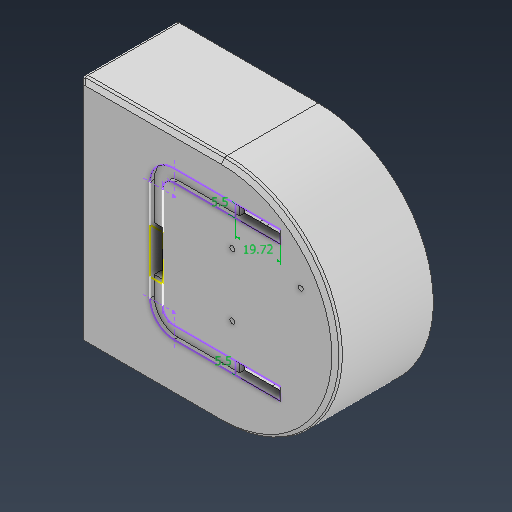
# Autodesk Inventor part: motor_housing
Saved by Autodesk Inventor 2026 (Build 300175050, 175E)
## iProperties
Created: 2025-09-28
Part Number: motor_housing
Material: Generic
Document SubType Name: Modeling
Designer: PK
Density: 1 g/cm^3
Appearance: Default
Author: PK
Autodesk Inventor part; units mm, degrees
ref_plane "YZ Plane" through (0, 0, 0) normal (1, 0, 0) x (0, 1, 0)
ref_plane "XZ Plane" through (0, 0, 0) normal (0, 1, 0) x (-1, 0, 0)
ref_plane "XY Plane" through (0, 0, 0) normal (0, 0, 1) x (1, 0, 0)
sketch "Sketch2" plane through (0, 0, 0) normal (0, 0, 1) x (1, 0, 0)
  line L0 (10.41, 16.56) -> (-35.41, 16.56)
  line L1 (-35.41, 16.56) -> (-35.41, -16.56)
  line L2 (-35.41, -12.56) -> (-25.61, -12.56)
  line L3 (-35.41, 12.56) -> (10.41, 12.56)
  line L4 (10.41, 16.56) -> (14.41, 16.56)
  line L5 (14.41, 16.56) -> (14.41, -16.56)
  line L6 (-35.41, 16.56) -> (-39.41, 16.56)
  line L7 (-39.41, 16.56) -> (-39.41, -16.56)
  circle A0 centre (0, 0) radius 3.15
  circle A1 centre (0, 0) radius 1.1
  line L8 (0.39, -12.56) -> (10.41, -12.56)
  line L9 (-5.61, -12.56) -> (0.39, -12.56)
  line L10 (-14.11, -12.56) -> (-5.61, -12.56)
  line L11 (-25.61, -12.56) -> (-14.11, -12.56)
  line L12 (-29.819493, 9.86) -> (-18.419493, 9.86)
  line L13 (-18.419493, 9.86) -> (-18.419493, -9.86)
  line L14 (-18.419493, -9.86) -> (-29.819493, -9.86)
  line L15 (-29.819493, -9.86) -> (-29.819493, 9.86)
  line L16 (-35.41, 12.56) -> (-29.819493, 12.56) construction
  line L17 (-35.41, -12.56) -> (-29.7, -12.56) construction
  line L18 (-35.41, -6.95) -> (-35.41, -12.56) construction
  line L19 (-18.419493, 9.86) -> (-11.119493, 9.86)
  line L20 (-11.119493, 9.86) -> (-11.119493, -9.86)
  line L21 (-11.119493, -9.86) -> (-18.419493, -9.86)
  line L22 (10.41, 12.56) -> (14.41, 12.56)
  line L23 (-35.41, 12.56) -> (-39.41, 12.56)
  line L24 (-35.41, -12.56) -> (-39.41, -12.56)
  line L25 (10.41, -12.56) -> (14.41, -12.56)
  arc A2 (-4.19, 9.107) -> (-7.707493, 6.41) centre (0, 0) ccw
  arc A3 (-7.707493, -6.41) -> (-4.19, -9.107) centre (0, 0) ccw
  line L26 (-4.19, 9.107) -> (-4.19, 12.56)
  line L27 (-7.707493, 6.41) -> (-11.119493, 6.41)
  line L28 (-7.707493, -6.41) -> (-11.119493, -6.41)
  line L29 (-4.19, -9.107) -> (-4.19, -12.56)
  line L30 (-16.619493, 9.86) -> (-16.619493, -9.86)
  line L31 (-29.819493, 7.86) -> (-34.007493, 7.86)
  line L32 (-34.007493, 7.86) -> (-34.007493, -7.86)
  line L33 (-34.007493, -7.86) -> (-29.819493, -7.86)
  line L34 (-34.007493, 7.86) -> (-35.41, 7.86)
  line L35 (-34.007493, -7.86) -> (-35.41, -7.86)
  line L36 (-11.119493, 9.86) -> (-11.119493, 12.56)
  line L37 (-11.119493, -9.86) -> (-11.119493, -12.56)
  line L38 (-29.819493, 9.86) -> (-29.819493, 12.56)
  line L39 (-29.819493, -9.86) -> (-29.819493, -12.56)
  line L40 (10.41, -9.76) -> (7.61, -12.56)
  line L41 (7.61, 12.56) -> (10.41, 9.76)
  line L42 (10.41, -16.56) -> (10.41, 16.56)
  line L43 (-39.41, -16.56) -> (14.41, -16.56)
  line L44 (16.988416, 21.396966) -> (51.988416, 21.396966)
  line L45 (51.988416, 21.396966) -> (51.988416, -23.603034)
  line L46 (51.988416, -23.603034) -> (16.988416, -23.603034)
  line L47 (16.988416, -23.603034) -> (16.988416, 21.396966)
  line L48 (14.09, -43.5) -> (-39.41, -43.5)
  line L49 (-39.41, -43.5) -> (-39.41, -20)
  line L50 (-39.41, -20) -> (14.09, -20)
  line L51 (14.09, -20) -> (14.09, -43.5)
  circle A4 centre (19.488416, 18.896966) radius 1.1
  circle A5 centre (49.488416, 18.896966) radius 1.05
  circle A6 centre (19.488416, -8.603034) radius 1.1
  circle A7 centre (3.59, -23) radius 1.875
  circle A8 centre (-30.31, -41.1) radius 1.875
  arc A9 (14.560353, -47) -> (14.560353, 47) centre (14.560353, 0) ccw
  line L52 (14.560353, -47) -> (-44.439647, -47)
  line L53 (-44.439647, -47) -> (-44.439647, 47)
  line L54 (-44.439647, 47) -> (14.560353, 47)
  arc A10 (14.560353, -50.5) -> (14.560353, 50.5) centre (14.560353, 0) ccw
  line L55 (14.560353, -50.5) -> (-47.939647, -50.5)
  line L56 (-47.939647, -50.5) -> (-47.939647, 50.5)
  line L57 (-47.939647, 50.5) -> (14.560353, 50.5)
  circle A11 centre (0, 0) radius 29
  arc A12 (-41.939636, -30.5) -> (-27.939647, -44.499989) centre (-27.922275, -30.482628) ccw construction
  arc A13 (-44.439634, -30.503098) -> (-27.942745, -46.999987) centre (-27.922275, -30.482628) ccw
  arc A14 (-39.439638, -30.496902) -> (-27.936549, -41.999991) centre (-27.922275, -30.482628) ccw
  arc A15 (-39.439638, -30.496902) -> (-44.439634, -30.503098) centre (-41.939636, -30.5) ccw
  arc A16 (-27.942745, -46.999987) -> (-27.936549, -41.999991) centre (-27.939647, -44.499989) ccw
  arc A17 (-27.939647, 44.499989) -> (-41.939636, 30.5) centre (-27.922275, 30.482628) ccw construction
  arc A18 (-27.942745, 46.999987) -> (-44.439634, 30.503098) centre (-27.922275, 30.482628) ccw
  arc A19 (-27.936549, 41.999991) -> (-39.439638, 30.496902) centre (-27.922275, 30.482628) ccw
  arc A20 (-27.936549, 41.999991) -> (-27.942745, 46.999987) centre (-27.939647, 44.499989) ccw
  arc A21 (-44.439634, 30.503098) -> (-39.439638, 30.496902) centre (-41.939636, 30.5) ccw
  arc A22 (14.663368, -44.34988) -> (14.662672, 44.349882) centre (14.560353, 0) ccw construction
  arc A23 (14.669175, -46.849874) -> (14.668439, 46.849875) centre (14.560353, 0) ccw
  arc A24 (14.657561, -41.849887) -> (14.656904, 41.849889) centre (14.560353, 0) ccw
  arc A25 (14.657561, -41.849887) -> (14.669175, -46.849874) centre (14.663368, -44.34988) ccw
  arc A26 (14.668439, 46.849875) -> (14.656904, 41.849889) centre (14.662672, 44.349882) ccw
  point P0 (14.41, 12.26)
  point P1 (14.41, -12.26)
  point P2 (10.11, 16.56)
  point P3 (-11.138042, -6.41)
  point P4 (-12.5, 16.56)
  point P5 (-39.41, 0)
  point P6 (-12.5, -16.56)
  point P7 (-35.41, -16.56)
  point P8 (51.98855, -21.103197)
  point P9 (19.488416, 21.396966)
  point P10 (51.988416, -21.103034)
  point P11 (49.488416, -23.603034)
  point P12 (51.988416, 18.896966)
  point P13 (49.488416, 21.396966)
  point P14 (51.988416, 18.896966)
  point P15 (20.855327, -23.603034)
  point P16 (51.988416, 6.396966)
  point P17 (14.09, -23)
  point P18 (3.59, -20)
  point P19 (-30.31, -43.5)
  point P20 (-39.41, -41.1)
  point P21 (-27.939647, -50.5)
  point P22 (-47.939647, -30.5)
  point P23 (-47.939647, 30.5)
  point P24 (-27.939647, 50.5)
  point P25 (34.488416, -1.103034)
  point P26 (34.488416, -23.603034)
  point P27 (16.988416, -1.103034)
  dimension "d5" = 4
  dimension "d72" = 25.12
  dimension "d83" = 11.4
  dimension "d112" = 4
  dimension "d184" = 6.3
  dimension "d185" = 2.2
  dimension "d210" = 0.3
  dimension "d211" = 0.3
  dimension "d228" = 0.3
  dimension "d244" = 3.412
  dimension "d245" = 3.412
  dimension "d254" = 5.5
  dimension "d255" = 2
  dimension "d256" = 2
  dimension "d257" = 4.188
  dimension "d272" = 7.3
  dimension "d292" = 2.8
  dimension "d293" = 2.8
  dimension "d294" = 2.8
  dimension "d295" = 2.8
  dimension "d319" = 12.56
  dimension "d320" = 11.8
  dimension "d322" = 3.453
  dimension "d323" = 3.453
  dimension "d328" = 6.15
  dimension "d330" = 2.7
  dimension "d331" = 2.7
  dimension "d358" = 45.82
  dimension "d359" = 4
  dimension "d360" = 4
  dimension "d361" = 4
  dimension "d362" = 4
  dimension "d433" = 35
  dimension "d434" = 45
  dimension "d435" = 53.5
  dimension "d436" = 23.5
  dimension "d438" = 2.5
  dimension "d439" = 2.5
  dimension "d440" = 2.5
  dimension "d441" = 2.2
  dimension "d442" = -12.5
  dimension "d443" = 2.2
  dimension "d444" = 3
  dimension "d445" = 10.5
  dimension "d446" = 2.4
  dimension "d447" = 9.1
  dimension "d448" = 3.75
  dimension "d449" = 3.75
  dimension "d450" = 3.5
  dimension "d451" = 2.1
  dimension "d457" = 58
  dimension "d462" = 94
  dimension "d463" = 59
  dimension "d464" = 5
  dimension "d465" = 5
  dimension "d466" = 20
  dimension "d467" = 20
  dimension "d468" = 20
  dimension "d469" = 20
  dimension "d470" = 5
  dimension "d511" = 0.15
  constraints: 116 end point, 48 point on line, 38 point on circle, 27 centre point, 22 perpendicular, 18 tangent, 9 parallel, 8 horizontal, 8 vertical alignment, 6 horizontal alignment, 5 coincident, 5 midpoint, 4 vertical, 1 collinear, 1 concentric, 3 other
  measures "d5" distance of L2.start L1.end
  measures "d72" distance between parallel lines of L11 L3
  measures "d83" distance of L13.end L14.end
  measures "d112" distance between parallel lines of L6 L23
  measures "d184" diameter of A0
  measures "d185" diameter of A1
  measures "d210" distance from line of L22 point (14.41, 12.26)
  measures "d211" distance from line of L25 point (14.41, -12.26)
  measures "d228" distance of point (10.11, 16.56) L0.start
  measures "d244" distance from line of L20 L27.start
  measures "d245" distance from line of L20 L28.start
  measures "d254" distance between parallel lines of L30 L20
  measures "d255" distance from line of L12 L31.start
  measures "d256" distance from line of L14 L33.end
  measures "d257" distance of L31.start L31.end
  measures "d272" distance between parallel lines of L13 L20
  measures "d292" distance of L41.start L3.end
  measures "d293" distance of L3.end L41.end
  measures "d294" distance of L40.start L8.end
  measures "d295" distance of L40.end L8.end
  measures "d319" distance from line of L3 A0.centre
  measures "d320" distance of L26.end L41.start
  measures "d322" distance of L26.start L26.end
  measures "d323" distance from line of L10 L29.start
  measures "d328" distance of L28.end L37.end
  measures "d330" distance of L36.end L19.end
  measures "d331" distance of L37.end L20.end
  measures "d358" distance of L0.start L0.end
  measures "d359" distance of L4.end L0.start
  measures "d360" distance of L6.end L0.end
  measures "d361" distance of L7.end L1.end
  measures "d362" distance of L5.end L42.start
  measures "d433" distance of L45.end L46.end
  measures "d434" distance of L44.end L45.end
  measures "d435" distance of L49.end L50.end
  measures "d436" distance of L48.end L49.end
  measures "d438" distance of L44.start point (19.488, 21.397)
  measures "d439" distance of L45.end point (51.988, -21.103)
  measures "d440" distance of L45.end point (49.488, -23.603)
  measures "d441" diameter of A4
  measures "d442" vertical distance of point (51.988, 6.397) A4.centre
  measures "d443" diameter of A6
  measures "d444" distance of L50.end point (14.09, -23)
  measures "d445" distance of point (3.59, -20) L50.end
  measures "d446" distance of point (-39.41, -41.1) L48.end
  measures "d447" distance of point (-30.31, -43.5) L48.end
  measures "d448" diameter of A7
  measures "d449" diameter of A8
  measures "d450" radial gap between concentric circles of A9 A10
  measures "d451" diameter of A5
  measures "d457" diameter of A11
  measures "d462" distance of L52.end L53.end
  measures "d463" distance of L52.start L52.end
  measures "d464" radial gap between concentric circles of A14 A13
  measures "d465" diameter of A21
  measures "d466" distance of L55.end point (-27.94, -50.5)
  measures "d467" distance of point (-47.94, -30.5) L55.end
  measures "d468" distance of L56.end point (-47.94, 30.5)
  measures "d469" distance of L56.end point (-27.94, 50.5)
  measures "d470" diameter of A26
  measures "d511" radial gap between concentric circles of A9 A23
extrude "Extrusion27" add sketch "Sketch2" along normal blind 10 contours L42 L3 A11 L0 | L4 L5 L22 L42 | A11 L3 L1 L0 | L42 L41 L3 | L22 L5 L25 L42 | L1 L23 L7 L6 | A11 L12 L38 L3 | L3 L36 L19 L12 A11 | L41 L42 L40 L8 L9 L29 A3 L28 L20 L27 A2 L26 L3 | L3 L38 L15 L31 L34 L1 | L1 L24 L7 L23 | L3 L26 A2 L27 L20 L36 | A11 L14 L15 L12 | L12 L13 L14 A11 | L5 L43 L42 L25 | L42 L8 L40 | L34 L32 L35 L1 | L20 L21 L30 L19 | L19 L30 L21 L13 | A11 L2 L39 L14 | L14 L21 L37 L10 L11 L2 A11 | L42 L43 A11 L2 L11 L10 L9 L8 | L35 L33 L15 L39 L2 L1 | L31 L15 L33 L32 | L24 L1 L43 L7 | A11 L43 L1 L2 | L28 A3 L29 L9 L10 L37 L20 | A0 | A1
extrude "Extrusion29" cut sketch "Sketch2" along normal blind 3.75 contours A11 L12 L38 L3 | L3 L36 L19 L12 A11 | L41 L42 L40 L8 L9 L29 A3 L28 L20 L27 A2 L26 L3 | L3 L38 L15 L31 L34 L1 | L3 L26 A2 L27 L20 L36 | A11 L14 L15 L12 | L12 L13 L14 A11 | L34 L32 L35 L1 | L20 L21 L30 L19 | L19 L30 L21 L13 | A11 L2 L39 L14 | L14 L21 L37 L10 L11 L2 A11 | L35 L33 L15 L39 L2 L1 | L31 L15 L33 L32 | L28 A3 L29 L9 L10 L37 L20 | A0 | A1
extrude "Extrusion31" cut sketch "Sketch2" along normal blind 3.75 from surface at 3.75 contours A0
extrude "Extrusion32" cut sketch "Sketch2" along normal blind 1.7 from surface at 3.75 contours A11 L12 L38 L3 | L3 L36 L19 L12 A11 | L3 L38 L15 L31 L34 L1 | L3 L26 A2 L27 L20 L36 | L34 L32 L35 L1 | A11 L2 L39 L14 | L14 L21 L37 L10 L11 L2 A11 | L35 L33 L15 L39 L2 L1 | L31 L15 L33 L32 | L28 A3 L29 L9 L10 L37 L20
extrude "Extrusion33" cut sketch "Sketch2" along normal up to surface (3.75 mm away) from surface at 3.75 contours A11 L14 L15 L12 | L12 L13 L14 A11 | L19 L30 L21 L13
extrude "Extrusion34" cut sketch "Sketch2" along normal blind 10 contours L20 L21 L30 L19
extrude "Extrusion35" add sketch "Sketch2" against normal blind 25.25 contours L42 L3 A11 L0 | L4 L5 L22 L42 | A11 L3 L1 L0 | L42 L41 L3 | L22 L5 L25 L42 | L1 L23 L7 L6 | L1 L24 L7 L23 | L5 L43 L42 L25 | L42 L8 L40 | L42 L43 A11 L2 L11 L10 L9 L8 | L24 L1 L43 L7 | A11 L43 L1 L2
extrude "Extrusion37" add sketch "Sketch2" along normal blind 4 from surface at 10 contours L42 L3 A11 L0 | L0 A11 L44 L47 L51 L50 L43 L5 L4 | L4 L5 L22 L42 | A11 L3 L1 L0 | L0 L6 L7 L43 A11 L50 L49 A14 A15 L53 A21 A19 A20 L54 A9 L52 A16 L48 A25 A23 A26 A24 L44 | L42 L41 L3 | L22 L5 L25 L42 | L1 L23 L7 L6 | A11 L47 L44 | L44 A24 L45 L46 L47 A11 | A11 L12 L38 L3 | L3 L36 L19 L12 A11 | L41 L42 L40 L8 L9 L29 A3 L28 L20 L27 A2 L26 L3 | L3 L38 L15 L31 L34 L1 | L1 L24 L7 L23 | A24 A26 A23 A25 L48 L51 L46 L45 L44 | L44 L45 A24 | L3 L26 A2 L27 L20 L36 | A11 L14 L15 L12 | L12 L13 L14 A11 | L5 L43 L42 L25 | L42 L8 L40 | L34 L32 L35 L1 | L47 L46 A24 A25 L51 A11 | A24 L45 | L20 L21 L30 L19 | L19 L30 L21 L13 | A11 L2 L39 L14 | L14 L21 L37 L10 L11 L2 A11 | L42 L43 A11 L2 L11 L10 L9 L8 | L35 L33 L15 L39 L2 L1 | L31 L15 L33 L32 | L24 L1 L43 L7 | A11 L50 L51 | L51 A25 L48 A16 A14 A8 L49 L50 A11 | L45 L46 A24 | A11 L43 L1 L2 | L51 L48 A25 | L28 A3 L29 L9 L10 L37 L20 | A16 A13 L48 | L48 A13 L49 A14 A8 A16 | L49 A13 A15 A14 | A13 L52 L53 L49 L48 | L48 L49 A13 | A14 A8 | A8 A14 | L53 L54 A18 | A18 A20 A19 A21 | A0 | A1 | A4 | A5 | A6 | A7 | L55 L56 L57 A10
extrude "Extrusion38" add sketch "Sketch2" against normal blind 42.55 from surface at 14 contours L55 L56 L57 A10
extrude "Extrusion39" add sketch "Sketch2" against normal blind 5 from surface at 10 contours A14 A8 | A8 A14 | A7
extrude "Extrusion40" cut sketch "Sketch2" along normal up to surface (4 mm away) from surface at 10 contours A4 | A5 | A6
extrude "Extrusion41" cut sketch "Sketch2" along normal up to surface (4 mm away) from surface at 10 contours L20 L21 L30 L19
sketch "Sketch20" plane through (-47.939647, -50.5, 10) normal (-1, 0, 0) x (0, 0, 1)
  line L0 (0, 3.5) -> (-38.55, 3.5) projected
  line L1 (-38.55, 97.5) -> (0, 97.5) projected
  line L2 (-35.25, 33.94) -> (0, 33.94) projected
  line L3 (0, 3.5) -> (0, 97.5) projected
  circle A0 centre (-12, 18.8) radius 6
  point P0 (-10, 50.5)
  point P1 (0, 18.8)
  point P2 (-12, 33.94)
  dimension "d509" = 12
  dimension "d510" = 12
  constraints: 2 point on line, 1 centre point, 1 coincident, 1 horizontal alignment, 1 vertical alignment
  measures "d509" distance of point (-12, 33.94) L2.end
  measures "d510" diameter of A0
extrude "Extrusion42" cut sketch "Sketch20" against normal up to surface (3.5 mm away)
extrude "Extrusion43" add sketch "Sketch2" against normal blind 6 from surface at -28.55 separate body contours A11 L3 L1 L0 | L0 L6 L7 L43 A11 L50 L49 A14 A15 L53 A21 A19 A20 L54 A9 L52 A16 L48 A25 A23 A26 A24 L44 | L1 L23 L7 L6 | L44 A24 L45 L46 L47 A11 | A11 L12 L38 L3 | L3 L38 L15 L31 L34 L1 | L1 L24 L7 L23 | A24 A26 A23 A25 L48 L51 L46 L45 L44 | L44 L45 A24 | A11 L14 L15 L12 | L34 L32 L35 L1 | L47 L46 A24 A25 L51 A11 | A24 L45 | A11 L2 L39 L14 | L35 L33 L15 L39 L2 L1 | L31 L15 L33 L32 | L24 L1 L43 L7 | L51 A25 L48 A16 A14 A8 L49 L50 A11 | L45 L46 A24 | A11 L43 L1 L2 | L51 L48 A25 | A16 A13 L48 | L48 A13 L49 A14 A8 A16 | L49 A13 A15 A14 | A13 L52 L53 L49 L48 | L48 L49 A13 | A14 A8 | A8 A14 | L53 L54 A18 | A18 A20 A19 A21 | A5 | L55 L56 L57 A10
extrude "Extrusion45" add sketch "Sketch2" along normal blind 5 from surface at -28.55 contours A24 A26 A23 A25 L48 L51 L46 L45 L44 | L44 L45 A24 | L45 L46 A24 | L51 L48 A25 | A16 A13 L48 | L48 A13 L49 A14 A8 A16 | L49 A13 A15 A14 | A14 A8 | A18 A20 A19 A21 picked at (-30.608888, -42.091797) bodies 2
fillet "Fillet18" radius 1.5 12 edges at (-39.41, 0, 10) (-12.5, -16.56, 10) (-12.5, 16.56, 10) (14.41, 0, 10) (-39.41, -16.56, -7.625) (-39.41, 16.56, -7.625) (14.41, 16.56, -7.625) (14.41, -16.56, -7.625) (-12.5, 16.56, -25.25) (-39.41, 0, -25.25) (-12.5, -16.56, -25.25) (14.41, 0, -25.25)
fillet "Fillet19" radius 1.5 6 edges at (10.41, -9.76, -10.75) (7.61, -12.56, -10.75) (10.41, 9.76, -10.75) (7.61, 12.56, -10.75) (-35.41, -12.56, -9.9) (-35.41, 12.56, -9.9)
fillet "Fillet20" radius 1.5 2 edges at (1.715, -23, 5) (-32.185, -41.1, 5)
fillet "Fillet22" radius 1.5 26 edges at (-47.9396, -50.5, -31.55) (-47.9396, 50.5, -31.55) (-39.6018, -42.1622, -28.55) (-41.9427, -28, -28.55) (-36.0663, -38.6266, -28.55) (-25.4396, -44.5031, -28.55) (12.1634, -44.3557, -28.55) (56.4104, 0.0003, -28.55) (12.1627, 44.3556, -28.55) (61.4104, 0.0004, -28.55) (-41.9427, 28, -28.55) (-39.6018, 42.1622, -28.55) (-25.4396, 44.5031, -28.55) (-36.0663, 38.6266, -28.55) (-39.6018, -42.1622, -23.55) (-41.9427, -28, -23.55) (-36.0663, -38.6266, -23.55) (-25.4396, -44.5031, -23.55) (12.1634, -44.3557, -23.55) (56.4104, 0.0003, -23.55) (12.1627, 44.3556, -23.55) (61.4104, 0.0004, -23.55) (-41.9427, 28, -23.55) (-39.6018, 42.1622, -23.55) (-25.4396, 44.5031, -23.55) (-36.0663, 38.6266, -23.55)
fillet "Fillet23" radius 1.5 6 edges at (-47.5003, 50.0607, -34.55) (-15.9396, 50.5, -34.55) (65.0604, 0, -34.55) (-15.9396, -50.5, -34.55) (-47.5003, -50.0607, -34.55) (-47.9396, 0, -34.55)
chamfer "Chamfer2" distance 2 angle 45 4 edges at (-47.9396, 0, 14) (-16.6896, 50.5, 14) (65.0604, 0, 14) (-16.6896, -50.5, 14)
fillet "Fillet24" radius 1.5 8 edges at (-47.9396, 0, 12) (65.0604, 0, 12) (-16.6896, -50.5, 12) (-16.6896, 50.5, 12) (-47.9396, 50.5, -8.275) (-46.9396, 49.5, 13) (-47.9396, -50.5, -8.275) (-46.9396, -49.5, 13)
sketch "Sketch21" plane through (14.560353, 0, 14) normal (0, 0, 1) x (1, 0, 0)
  line L0 (-25.679846, 9.86) -> (-25.679846, -9.86)
  line L1 (-31.179846, 9.86) -> (-25.679846, 9.86)
  line L2 (-31.179846, -9.86) -> (-31.179846, 9.86)
  line L3 (-25.679846, -9.86) -> (-31.179846, -9.86)
  line L4 (26, 36.636833) -> (6.28, 36.636833)
  line L5 (6.28, 36.636833) -> (6.28, 31.136833)
  line L6 (6.28, 31.136833) -> (26, 31.136833)
  line L7 (26, 31.136833) -> (26, 36.636833)
  line L8 (6.28, 36.636833) -> (-20.751971, 36.636833)
  line L9 (6.28, 31.136833) -> (-20.679846, 31.136833)
  line L10 (26, -23) -> (6.28, -23)
  line L11 (6.28, -23) -> (6.28, -28.5)
  line L12 (6.28, -28.5) -> (26, -28.5)
  line L13 (26, -28.5) -> (26, -23)
  line L14 (6.28, -28.5) -> (-20.679846, -28.5)
  line L15 (6.28, -23) -> (-20.679846, -23)
  arc A0 (-20.679846, 31.136833) -> (-25.679846, 26.136833) centre (-20.679846, 26.136833) ccw
  arc A1 (-20.679846, 36.636833) -> (-31.179846, 26.136833) centre (-20.715908, 26.172896) ccw
  arc A2 (-25.679846, -18) -> (-20.679846, -23) centre (-20.679846, -18) ccw
  arc A3 (-31.179846, -18) -> (-20.679846, -28.5) centre (-20.679846, -18) ccw
  line L16 (-31.179846, 26.208958) -> (-31.179846, 9.86)
  line L17 (-25.679846, 26.136833) -> (-25.679846, 9.86)
  line L18 (-25.679846, -18) -> (-25.679846, -9.86)
  line L19 (-31.179846, -18) -> (-31.179846, -9.86)
  dimension "d518" = 19.72
  dimension "d519" = 5.5
  dimension "d520" = 5.5
  constraints: 32 end point, 10 point on circle, 6 perpendicular, 5 horizontal, 5 parallel, 4 centre point, 4 vertical alignment, 3 tangent, 2 horizontal alignment, 2 point on line
  measures "d518" distance of L6.end L5.end
  measures "d519" distance of L5.end L4.end
  measures "d520" distance of L11.end L10.end
extrude "Extrusion46" cut sketch "Sketch21" against normal up to surface (4 mm away) contours L5 L4 L7 L6 | L10 L13 L12 L11 bodies 1
extrude "Extrusion47" cut sketch "Sketch21" against normal blind 1.8 contours L1 L16 A1 L8 L5 L9 A0 L17 | L18 A2 L15 L11 L14 A3 L19 L3 bodies 1
body "Solid2"
body "Solid3"
